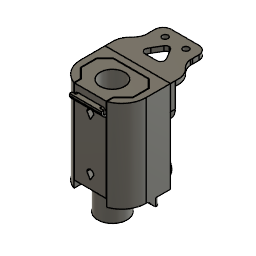
GCodeScribe-Ai3MS-v2 (Autodesk Fusion 360 design; units mm, degrees)
Autodesk Fusion 360 part; units mm, degrees
sketch "Skizze1" plane through (0, 0, 0) normal (0, 0, 1) x (1, 0, 0)
  circle A0 centre (-21.4, -45) radius 3
  circle A1 centre (10.4, -45) radius 3
  line L0 (10.4, -17.9) -> (12.7094, -15.1149)
  line L1 (10.4, -17.9) -> (8.0906, -15.1149)
  line L2 (10.4, -47.9) -> (11.8113, -46.1172)
  line L3 (10.4, -47.9) -> (8.9887, -46.1172)
  line L4 (-21.4, -47.9) -> (-19.9887, -46.1172)
  line L5 (-21.4, -47.9) -> (-22.8113, -46.1172)
  line L6 (0, 3) -> (20, 3)
  line L7 (0, 3) -> (-20, 3)
  line L8 (0, -52.5) -> (10, -52.5)
  line L9 (0, -52.5) -> (-21, -52.5)
  line L10 (-18, -16) -> (-18, -9)
  line L11 (-20, 3) -> (-20, -2)
  line L12 (20, 3) -> (20, -12)
  spline S0 degree 5 poles (-20, -2) (-19.9962, -2.1382) (-19.9821, -2.4102) (-19.9417, -2.805) (-19.8459, -3.3161) (-19.6426, -3.9884) (-19.3553, -4.7231) (-18.9981, -5.5245) (-18.6487, -6.2255) (-18.379, -6.7307) (-18.1914, -7.1991) (-18.0954, -7.7141) (-18.042, -8.2765) (-18.0129, -8.7435) (-18, -9) knots 0 0 0 0 0 0 0.1 0.2 0.3 0.4 0.5 0.6 0.7 0.8 0.9 1 1 1 1 1 1
  line L13 (-19.3517, -4.7497) -> (-18.6483, -6.2503)
  line L14 (-20.0191, -1.3059) -> (-19.9809, -2.6941)
  line L15 (-18.065, -7.7085) -> (-17.935, -10.2915)
  spline S1 degree 5 poles (-18, -16) (-18.0015, -16.1229) (-18.0072, -16.3686) (-18.0241, -16.7364) (-18.0635, -17.2253) (-18.1429, -17.8339) (-18.255, -18.4398) (-18.4023, -19.0426) (-18.5862, -19.6424) (-18.805, -20.2392) (-19.0559, -20.8333) (-19.2802, -21.3065) (-19.4608, -21.6604) (-19.5866, -21.8959) (-19.6509, -22.0135) knots 0 0 0 0 0 0 0.1 0.2 0.3 0.4 0.5 0.6 0.7 0.8 0.9 1 1 1 1 1 1
  spline S2 degree 5 poles (-21.2455, -30.2376) (-21.2309, -30.4269) (-21.205, -30.8022) (-21.1761, -31.3543) (-21.1617, -32.0688) (-21.2087, -32.9229) (-21.3505, -33.7345) (-21.6131, -34.4999) (-22.0109, -35.2163) (-22.5348, -35.8831) (-23.1534, -36.5016) (-23.8233, -37.0744) (-24.4963, -37.6045) (-25.1269, -38.0951) (-25.6805, -38.5493) (-26.1397, -38.9694) (-26.426, -39.2798) (-26.5947, -39.4985) (-26.6869, -39.6381) (-26.728, -39.7064) knots 0 0 0 0 0 0 0.066667 0.133333 0.2 0.266667 0.333333 0.4 0.466667 0.533333 0.6 0.666667 0.733333 0.8 0.866667 0.933333 1 1 1 1 1 1
  line L16 (-21.3577, -28.7828) -> (-21.1334, -31.6924)
  spline S3 degree 5 poles (20, -12) (19.9902, -12.2537) (19.9583, -12.7517) (19.8731, -13.4705) (19.6847, -14.3722) (19.3259, -15.4053) (18.8498, -16.3464) (18.2695, -17.2007) (17.6094, -17.9783) (16.9043, -18.6958) (16.1934, -19.3801) (15.5157, -20.0708) (14.9046, -20.8255) (14.3839, -21.7174) (13.9694, -22.8146) (13.6688, -24.1621) (13.4822, -25.7646) (13.4024, -27.5617) (13.4166, -29.4387) (13.5126, -31.2683) (13.6808, -32.9342) (13.9233, -34.3811) (14.247, -35.6094) (14.6958, -36.8028) (15.2662, -38.0648) (15.8927, -39.3316) (16.3745, -40.2602) (16.6918, -40.8543) (16.8792, -41.197) (16.9669, -41.3551) knots 0 0 0 0 0 0 0.04 0.08 0.12 0.16 0.2 0.24 0.28 0.32 0.36 0.4 0.44 0.48 0.52 0.56 0.6 0.64 0.68 0.72 0.76 0.8 0.84 0.88 0.92 0.96 1 1 1 1 1 1
  line L17 (15.8541, -39.3501) -> (18.0798, -43.3601)
  line L18 (13.4229, -32.7877) -> (15.038, -38.1064)
  arc A2 (-19.3409, -21.4198) -> (-21.2455, -30.2376) centre (-5.5, -29.024) ccw
  arc A3 (-26.728, -39.7064) -> (-21, -52.5) centre (-21.4, -45) ccw
  arc A4 (10, -52.5) -> (16.9669, -41.3551) centre (10.4, -45) ccw
  arc A5 (12.7094, -15.1149) -> (8.0906, -15.1149) centre (10.4, -13.2) ccw
  arc A6 (11.8113, -46.1172) -> (8.9887, -46.1172) centre (10.4, -45) ccw
  arc A7 (-19.9887, -46.1172) -> (-22.8113, -46.1172) centre (-21.4, -45) ccw
  line L19 (-5.5, -46) -> (2.9593, -36.8144)
  line L20 (-5.5, -46) -> (-13.9593, -36.8144)
  arc A8 (2.9593, -36.8144) -> (-13.9593, -36.8144) centre (-5.5, -29.024) ccw
  point P0 (-19, -5.5)
  point P1 (-18.4, -19)
  point P2 (-21.8, -34.8)
  point P3 (-25, -38)
  point P4 (18.5235, -16.7998)
  point P5 (15.7176, -19.8821)
  point P6 (13.6059, -24.8553)
  point P7 (14.2304, -35.447)
  dimension "d1" = 3
  dimension "d4" = 52.5
  dimension "d5" = 31.8
  dimension "d6" = 6
  dimension "d7" = 6
  constraint concentric A0 A7
  constraint concentric A1 A6
  constraint tangent L0 A5
  constraint tangent L1 A5
  constraint tangent L2 A6
  constraint tangent L3 A6
  constraint tangent L4 A7
  constraint tangent L5 A7
  constraint perpendicular L7 L10
  constraint perpendicular L7 L11
  constraint perpendicular L6 L12
  constraint midpoint P0 L13
  constraint midpoint L11.end L14
  constraint midpoint L10.end L15
  constraint concentric A2 A8
  constraint coincident S1.end A2
  constraint concentric A0 A3
  constraint concentric A4 A6
  constraint midpoint S2.start L16
  constraint tangent L16 A2
  constraint midpoint S3.end L17
  constraint tangent L17 A4
  constraint midpoint P7 L18
  constraint coincident S1 A2.start
  constraint tangent L19 A8
  constraint tangent L20 A8
  measures "d1" distance of origin L6.start
  measures "d4" distance of origin L8.start
  measures "d5" distance of A1.centre A0.centre
  measures "d6" diameter of A0
  measures "d7" diameter of A1
extrude "Extrusion1" add sketch "Skizze1" against normal blind 3 contours L6 L7 L8 L9 L10 L11 L12 S0 S1 S2 S3 A2 A3 A4 makes body 1
extrude "Extrusion2" add sketch "Skizze1" along normal blind -3 and the other way blind 1 contours A0 | A1 bodies 1
chamfer "Fase1" distance 1 angle 45 2 edges at (-24.197, -43.9152, 0) (7.603, -43.9152, 0) tangent chain off on bodies 1
sketch "Skizze3" plane through (0, 3, 0) normal (0, 1, 0) x (-1, 0, 0)
  line L0 (20, 0) -> (-20, 0)
  line L1 (-20, 0) -> (-20, -3)
  line L2 (-20, -3) -> (20, -3)
  line L3 (20, -3) -> (20, 0)
  circle A0 centre (6.3, -23.1) radius 1.8
  circle A1 centre (-6.35, -23.1) radius 1.8
  line L4 (13.5, -18.7516) -> (13.5, -24)
  spline S0 degree 5 poles (8.5, -29) (8.6225, -29) (8.8744, -28.9898) (9.2731, -28.944) (9.8406, -28.8204) (10.5757, -28.5537) (11.2933, -28.1664) (11.9495, -27.6548) (12.5089, -27.0273) (12.9534, -26.312) (13.2741, -25.5451) (13.4289, -24.9193) (13.4871, -24.4559) (13.5, -24.1512) (13.5, -24) knots 0 0 0 0 0 0 0.1 0.2 0.3 0.4 0.5 0.6 0.7 0.8 0.9 1 1 1 1 1 1
  line L5 (13.5, -24.8) -> (13.5, -23.2)
  line L6 (7.8, -29) -> (9.2, -29)
  spline S1 degree 5 poles (13.5, -20) (13.5, -19.9292) (13.4971, -19.7541) (13.4842, -19.3915) (13.4737, -18.7163) (13.5884, -17.6135) (13.9445, -16.3468) (14.5844, -15.0442) (15.4313, -13.8595) (16.179, -12.9859) (16.756, -12.4009) (17.1969, -11.9798) (17.5969, -11.5513) (18.0425, -10.9683) (18.5401, -10.1859) (19.0328, -9.246) (19.447, -8.2461) (19.7218, -7.2982) (19.8588, -6.5279) (19.9339, -5.9739) (19.9737, -5.4171) (19.9917, -4.7412) (19.9985, -3.9829) (20, -3.3491) (20, -3) knots 0 0 0 0 0 0 0.05 0.1 0.15 0.2 0.25 0.3 0.35 0.4 0.45 0.5 0.55 0.6 0.65 0.7 0.75 0.8 0.85 0.9 0.95 1 1 1 1 1 1
  line L7 (20, -7) -> (20, 1)
  line L8 (13.3963, -16.8526) -> (16.6037, -12.1474)
  line L9 (13.5, -20.6696) -> (13.5, -19.3304)
  line L10 (19.3454, -8.9015) -> (20.128, -5.3644)
  line L11 (8.5, -29) -> (0, -29)
  line L12 (0, -29) -> (0, 0)
  line L13 (-8.5, -29) -> (0, -29)
  spline S2 degree 5 poles (-8.5, -29) (-8.6225, -29) (-8.8744, -28.9898) (-9.2731, -28.944) (-9.8406, -28.8204) (-10.5757, -28.5537) (-11.2933, -28.1664) (-11.9495, -27.6548) (-12.5089, -27.0273) (-12.9534, -26.312) (-13.2741, -25.5451) (-13.4289, -24.9193) (-13.4871, -24.4559) (-13.5, -24.1512) (-13.5, -24) knots 0 0 0 0 0 0 0.1 0.2 0.3 0.4 0.5 0.6 0.7 0.8 0.9 1 1 1 1 1 1
  line L14 (-7.8, -29) -> (-9.2, -29)
  line L15 (-13.5, -24.8) -> (-13.5, -23.2)
  line L16 (-13.5, -18.7516) -> (-13.5, -24)
  spline S3 degree 5 poles (-13.5, -20) (-13.5, -19.9292) (-13.4971, -19.7541) (-13.4842, -19.3915) (-13.4737, -18.7163) (-13.5884, -17.6135) (-13.9445, -16.3468) (-14.5844, -15.0442) (-15.4313, -13.8595) (-16.179, -12.9859) (-16.756, -12.4009) (-17.1969, -11.9798) (-17.5969, -11.5513) (-18.0425, -10.9683) (-18.5401, -10.1859) (-19.0328, -9.246) (-19.447, -8.2461) (-19.7218, -7.2982) (-19.8588, -6.5279) (-19.9339, -5.9739) (-19.9737, -5.4171) (-19.9917, -4.7412) (-19.9985, -3.9829) (-20, -3.3491) (-20, -3) knots 0 0 0 0 0 0 0.05 0.1 0.15 0.2 0.25 0.3 0.35 0.4 0.45 0.5 0.55 0.6 0.65 0.7 0.75 0.8 0.85 0.9 0.95 1 1 1 1 1 1
  line L17 (-13.5, -20.6696) -> (-13.5, -19.3304)
  line L18 (-13.3963, -16.8526) -> (-16.6037, -12.1474)
  line L19 (-19.3454, -8.9015) -> (-20.128, -5.3644)
  line L20 (-20, -7) -> (-20, 1)
  line L21 (20, -3) -> (-20, -3)
  line L22 (0, -8) -> (-4, -8)
  line L23 (-5, -13) -> (-2, -18)
  spline S4 degree 5 poles (-4, -8) (-4.0989, -8) (-4.2956, -8.0243) (-4.5872, -8.1338) (-4.9651, -8.4053) (-5.3965, -8.8504) (-5.7532, -9.3091) (-5.9981, -9.7274) (-6.0873, -10.2022) (-6.0148, -10.7812) (-5.7969, -11.4575) (-5.5261, -12.0559) (-5.279, -12.5228) (-5.096, -12.8399) (-5, -13) knots 0 0 0 0 0 0 0.1 0.2 0.3 0.4 0.5 0.6 0.7 0.8 0.9 1 1 1 1 1 1
  spline S5 degree 5 poles (-2, -18) (-1.9518, -18.067) (-1.8575, -18.1956) (-1.7217, -18.372) (-1.5525, -18.5738) (-1.3612, -18.7681) (-1.1888, -18.9058) (-1.0316, -18.9925) (-0.8802, -19.0487) (-0.7186, -19.1024) (-0.5304, -19.153) (-0.3459, -19.1844) (-0.1831, -19.1972) (-0.063, -19.2) (0, -19.2) knots 0 0 0 0 0 0 0.1 0.2 0.3 0.4 0.5 0.6 0.7 0.8 0.9 1 1 1 1 1 1
  line L24 (-0.3974, -19.2) -> (0.3974, -19.2)
  line L25 (-1.1683, -18.9262) -> (-0.8317, -19.0738)
  line L26 (-3.5, -8) -> (-4.5, -8)
  line L27 (-5.4264, -12.2893) -> (-4.5736, -13.7107)
  line L28 (-5.7067, -9.1954) -> (-6.0933, -10.0046)
  spline S6 degree 5 poles (2, -18) (1.9518, -18.067) (1.8575, -18.1956) (1.7217, -18.372) (1.5525, -18.5738) (1.3612, -18.7681) (1.1888, -18.9058) (1.0316, -18.9925) (0.8802, -19.0487) (0.7186, -19.1024) (0.5304, -19.153) (0.3459, -19.1844) (0.1831, -19.1972) (0.063, -19.2) (0, -19.2) knots 0 0 0 0 0 0 0.1 0.2 0.3 0.4 0.5 0.6 0.7 0.8 0.9 1 1 1 1 1 1
  line L29 (-2.2394, -17.6668) -> (-1.7606, -18.3332)
  line L30 (2.2394, -17.6668) -> (1.7606, -18.3332)
  line L31 (1.1683, -18.9262) -> (0.8317, -19.0738)
  line L32 (0.3974, -19.2) -> (-0.3974, -19.2)
  line L33 (5, -13) -> (2, -18)
  spline S7 degree 5 poles (4, -8) (4.0989, -8) (4.2956, -8.0243) (4.5872, -8.1338) (4.9651, -8.4053) (5.3965, -8.8504) (5.7532, -9.3091) (5.9981, -9.7274) (6.0873, -10.2022) (6.0148, -10.7812) (5.7969, -11.4575) (5.5261, -12.0559) (5.279, -12.5228) (5.096, -12.8399) (5, -13) knots 0 0 0 0 0 0 0.1 0.2 0.3 0.4 0.5 0.6 0.7 0.8 0.9 1 1 1 1 1 1
  line L34 (3.5, -8) -> (4.5, -8)
  line L35 (5.7067, -9.1954) -> (6.0933, -10.0046)
  line L36 (5.4264, -12.2893) -> (4.5736, -13.7107)
  line L37 (0, -8) -> (4, -8)
  point P0 (11.8587, -27.6874)
  point P1 (15, -14.5)
  point P2 (17.7, -11.4)
  point P3 (19.7367, -7.1329)
  point P4 (-11.8587, -27.6874)
  point P5 (-15, -14.5)
  point P6 (-17.7, -11.4)
  point P7 (-19.7367, -7.1329)
  point P8 (-5.9, -9.6)
  point P9 (-1, -19)
  point P10 (1, -19)
  point P11 (5.9, -9.6)
  dimension "d15" = 12.65
  dimension "d16" = 3.6
  constraint midpoint L4.end L5
  constraint midpoint S0.start L6
  constraint coincident L4 S1.start
  constraint midpoint L2.end L7
  constraint midpoint P1 L8
  constraint midpoint S1.start L9
  constraint coincident S1 L4.start
  constraint midpoint P3 L10
  constraint parallel L2 L11
  constraint coincident L12.end origin
  constraint perpendicular L0 L12
  constraint symmetric S0.start L12 L13.start
  constraint symmetric P0 L12 P4
  constraint symmetric L4.end L12 S2.end
  constraint symmetric L5.start L12 L15.start
  constraint symmetric L5.end L12 L15.end
  constraint symmetric L6.start L12 L14.start
  constraint symmetric L6.end L12 L14.end
  constraint symmetric S1.start L12 S3.start
  constraint symmetric P1 L12 P5
  constraint symmetric P2 L12 P6
  constraint symmetric P3 L12 P7
  constraint symmetric L2.end L12 L1.end
  constraint symmetric L7.start L12 L20.start
  constraint symmetric L7.end L12 L20.end
  constraint symmetric L8.start L12 L18.start
  constraint symmetric L8.end L12 L18.end
  constraint symmetric L9.start L12 L17.start
  constraint symmetric L9.end L12 L17.end
  constraint symmetric L4.start L12 L16.start
  constraint symmetric L10.start L12 L19.start
  constraint symmetric L10.end L12 L19.end
  constraint symmetric L11.end L12 L13.end
  constraint coincident L12 L22.start
  constraint perpendicular L12 L22
  constraint coincident L12 S5.end
  constraint midpoint S5.end L24
  constraint midpoint P9 L25
  constraint midpoint L22.end L26
  constraint midpoint L23.start L27
  constraint coincident L23 L27.end
  constraint midpoint P8 L28
  constraint midpoint L23.end L29
  constraint symmetric L12 L22.start L37.start
  constraint symmetric L12 L22.end S7.start
  constraint symmetric L12 L23.start L33.start
  constraint symmetric L12 L23.end S6.start
  constraint symmetric L12 P8 P11
  constraint symmetric L12 P9 P10
  constraint symmetric L12 S5.end S6.end
  constraint symmetric L12 L24.start L24.end
  constraint symmetric L12 L24.end L24.start
  constraint symmetric L12 L25.start L31.start
  constraint symmetric L12 L25.end L31.end
  constraint symmetric L12 L26.start L34.start
  constraint symmetric L12 L26.end L34.end
  constraint symmetric L12 L27.start L36.start
  constraint symmetric L12 L27.end L36.end
  constraint symmetric L12 L28.start L35.start
  constraint symmetric L12 L28.end L35.end
  constraint symmetric L12 L29.start L30.start
  constraint symmetric L12 L29.end L30.end
  measures "d15" distance of A0.centre A1.centre
  measures "d16" diameter of A1
extrude "Extrusion3" add sketch "Skizze3" against normal blind 3 contours L2 L4 S0 L5 L6 S1 L9 L11 L12 L21 S6 L33 S7 L34 L36 L37 | L2 L12 L13 S2 L14 L15 L16 S3 L17 L21 L22 L23 S4 S5 L26 L27 bodies 1
sketch "Skizze4" plane through (0, 0, 0) normal (0, 0, 1) x (1, 0, 0)
  circle A0 centre (-21.4, -45) radius 4
  line L0 (12.7094, -15.1149) -> (10.4, -17.9)
  line L1 (10.4, -17.9) -> (8.0906, -15.1149)
  arc A1 (12.7094, -15.1149) -> (8.0906, -15.1149) centre (10.4, -13.2) ccw
  line L2 (-21, -52.5) -> (10, -52.5)
  arc A2 (10, -52.5) -> (16.9669, -41.3551) centre (10.4, -45) ccw
  spline S0 degree 5 poles (20, -12) (19.9902, -12.2537) (19.9583, -12.7517) (19.8731, -13.4705) (19.6847, -14.3722) (19.3259, -15.4053) (18.8498, -16.3464) (18.2695, -17.2007) (17.6094, -17.9783) (16.9043, -18.6958) (16.1934, -19.3801) (15.5157, -20.0708) (14.9046, -20.8255) (14.3839, -21.7174) (13.9694, -22.8146) (13.6688, -24.1621) (13.4822, -25.7646) (13.4024, -27.5617) (13.4166, -29.4387) (13.5126, -31.2683) (13.6808, -32.9342) (13.9233, -34.3811) (14.247, -35.6094) (14.6958, -36.8028) (15.2662, -38.0648) (15.8927, -39.3316) (16.3745, -40.2602) (16.6918, -40.8543) (16.8792, -41.197) (16.9669, -41.3551) knots 0 0 0 0 0 0 0.04 0.08 0.12 0.16 0.2 0.24 0.28 0.32 0.36 0.4 0.44 0.48 0.52 0.56 0.6 0.64 0.68 0.72 0.76 0.8 0.84 0.88 0.92 0.96 1 1 1 1 1 1
  line L3 (20, -12) -> (20, 3)
  line L4 (20, 3) -> (-20, 3)
  line L5 (-20, 3) -> (-20, -2)
  spline S1 degree 5 poles (-20, -2) (-19.9962, -2.1382) (-19.9821, -2.4102) (-19.9417, -2.805) (-19.8459, -3.3161) (-19.6426, -3.9884) (-19.3553, -4.7231) (-18.9981, -5.5245) (-18.6487, -6.2255) (-18.379, -6.7307) (-18.1914, -7.1991) (-18.0954, -7.7141) (-18.042, -8.2765) (-18.0129, -8.7435) (-18, -9) knots 0 0 0 0 0 0 0.1 0.2 0.3 0.4 0.5 0.6 0.7 0.8 0.9 1 1 1 1 1 1
  line L6 (-18, -9) -> (-18, -16)
  spline S2 degree 5 poles (-18, -16) (-18.0015, -16.1229) (-18.0072, -16.3686) (-18.0241, -16.7364) (-18.0635, -17.2253) (-18.1429, -17.8339) (-18.255, -18.4398) (-18.4023, -19.0426) (-18.5862, -19.6424) (-18.8046, -20.2383) (-19.0049, -20.7127) (-19.1683, -21.0671) (-19.2826, -21.3026) (-19.3409, -21.4198) knots 0 0 0 0 0 0 0.1 0.2 0.3 0.4 0.5 0.6 0.7 0.8 0.899242 0.899242 0.899242 0.899242 0.899242 0.899242
  spline S3 degree 5 poles (-19.3409, -21.4198) (-19.3414, -21.4207) (-19.4006, -21.5397) (-19.4612, -21.6585) (-19.5232, -21.7773) (-19.5866, -21.8959) (-19.6509, -22.0135) knots 0.899242 0.899242 0.899242 0.899242 0.899242 0.899242 0.9 1 1 1 1 1 1
  arc A3 (-19.6509, -22.0135) -> (-21.2455, -30.2376) centre (-5.5, -29.024) ccw
  spline S4 degree 5 poles (-21.2455, -30.2376) (-21.2309, -30.4269) (-21.205, -30.8022) (-21.1761, -31.3543) (-21.1617, -32.0688) (-21.2087, -32.9229) (-21.3505, -33.7345) (-21.6131, -34.4999) (-22.0109, -35.2163) (-22.5348, -35.8831) (-23.1534, -36.5016) (-23.8233, -37.0744) (-24.4963, -37.6045) (-25.1269, -38.0951) (-25.6805, -38.5493) (-26.1397, -38.9694) (-26.426, -39.2798) (-26.5947, -39.4985) (-26.6869, -39.6381) (-26.728, -39.7064) knots 0 0 0 0 0 0 0.066667 0.133333 0.2 0.266667 0.333333 0.4 0.466667 0.533333 0.6 0.666667 0.733333 0.8 0.866667 0.933333 1 1 1 1 1 1
  arc A4 (-26.728, -39.7064) -> (-21, -52.5) centre (-21.4, -45) ccw
  circle A5 centre (10.4, -45) radius 4
  line L7 (2.9593, -36.8144) -> (-5.5, -46)
  line L8 (-5.5, -46) -> (-13.9593, -36.8144)
  arc A6 (2.9593, -36.8144) -> (-13.9593, -36.8144) centre (-5.5, -29.024) ccw
  line L9 (2, -49.5) -> (3.7496, -47.7857)
  line L10 (2, -49.5) -> (0.2504, -47.7857)
  line L11 (10, -40.5) -> (11.7496, -38.7857)
  line L12 (10, -40.5) -> (8.2504, -38.7857)
  line L13 (10, -25.5) -> (11.7496, -23.7857)
  line L14 (10, -25.5) -> (8.2504, -23.7857)
  line L15 (14, -7.5) -> (15.7496, -5.7857)
  line L16 (14, -7.5) -> (12.2504, -5.7857)
  line L17 (-14, -7.5) -> (-12.2504, -5.7857)
  line L18 (-14, -7.5) -> (-15.7496, -5.7857)
  arc A7 (-12.2504, -5.7857) -> (-15.7496, -5.7857) centre (-14, -4) ccw
  arc A8 (15.7496, -5.7857) -> (12.2504, -5.7857) centre (14, -4) ccw
  arc A9 (11.7496, -23.7857) -> (8.2504, -23.7857) centre (10, -22) ccw
  arc A10 (11.7496, -38.7857) -> (8.2504, -38.7857) centre (10, -37) ccw
  arc A11 (3.7496, -47.7857) -> (0.2504, -47.7857) centre (2, -46) ccw
  arc A12 (-11.2504, -47.7857) -> (-14.7496, -47.7857) centre (-13, -46) ccw
  line L19 (-13, -49.5) -> (-11.2504, -47.7857)
  line L20 (-13, -49.5) -> (-14.7496, -47.7857)
  dimension "d20" = 5
  dimension "d21" = 5
  dimension "d22" = 5
  dimension "d23" = 5
  dimension "d29" = 3.5
  dimension "d30" = 3.5
  dimension "d31" = 3.5
  dimension "d32" = 3.5
  dimension "d33" = 3.5
  dimension "d125" = 5
  dimension "d126" = 3.5
  constraint tangent L9 A11
  constraint tangent L10 A11
  constraint tangent L11 A10
  constraint tangent L12 A10
  constraint tangent L13 A9
  constraint tangent L14 A9
  constraint tangent L15 A8
  constraint tangent L16 A8
  constraint tangent L17 A7
  constraint tangent L18 A7
  constraint tangent A12 L19
  constraint tangent A12 L20
  measures "d20" diameter of A9
  measures "d21" diameter of A8
  measures "d22" diameter of A7
  measures "d23" diameter of A11
  measures "d29" distance of A9.centre L13.start
  measures "d30" distance of A8.centre L15.start
  measures "d31" distance of A7.centre L17.start
  measures "d32" distance of A10.centre L11.start
  measures "d33" distance of A11.centre L9.start
  measures "d125" diameter of A12
  measures "d126" distance of A12.centre L19.start
extrude "Extrusion4" cut sketch "Skizze4" against normal blind 2 contours L9 L10 A11 | L11 L12 A10 | L13 L14 A9 | L15 L16 A8 | L17 L18 A7 | A12 L19 L20 bodies 1
chamfer "Fase2" distance 0.3 angle 45 18 edges at (1.1252, -48.6429, 0) (2, -43.5, 0) (2.8748, -48.6429, 0) (9.1252, -39.6429, 0) (10, -34.5, 0) (10.8748, -39.6429, 0) (9.1252, -24.6429, 0) (10, -19.5, 0) (10.8748, -24.6429, 0) (13.1252, -6.6429, 0) (14, -1.5, 0) (14.8748, -6.6429, 0) (-13.1252, -6.6429, 0) (-14, -1.5, 0) (-14.8748, -6.6429, 0) (-13, -43.5, 0) (-12.1252, -48.6429, 0) (-13.8748, -48.6429, 0) tangent chain off on bodies 1
sketch "Skizze6" plane through (0, 0, 0) normal (0, 0, 1) x (1, 0, 0)
  line L0 (-20, 0) -> (-20, -53)
  line L1 (-20, -53) -> (20, -53)
  line L2 (20, -53) -> (20, 0)
  line L3 (-20, 0) -> (-20, 3)
  line L4 (-20, 3) -> (20, 3)
  line L5 (20, 3) -> (20, 0)
  line L6 (-20, -50) -> (20, -50)
  line L7 (-20, 3) -> (-20, 6)
  line L8 (-20, 6) -> (20, 6)
  line L9 (20, 6) -> (20, 3)
  constraint vertical L0
  constraint horizontal L1
  constraint vertical L2
  constraint perpendicular L3 L4
  constraint coincident L0 L6.start
  constraint coincident L2 L6.end
  constraint perpendicular L2 L6
  constraint perpendicular L4 L7
  constraint perpendicular L3 L8
  constraint perpendicular L4 L9
extrude "Extrusion8" add sketch "Skizze6" along normal blind 4 separate body contours L0 L2 L3 L4 L5 L6 | L0 L1 L2 L6 makes body 2
extrude "Extrusion9" cut sketch "Skizze1" along normal blind 3 contours A0 | A1 | L0 L1 A5 | L2 L3 A6 | L4 L5 A7 bodies 2
extrude "Extrusion10" cut sketch "Skizze4" along normal blind 2.5 contours L9 L10 A11 | L11 L12 A10 | L13 L14 A9 | L15 L16 A8 | L17 L18 A7 | A12 L19 L20 bodies 2
chamfer "Fase3" distance 0.5 angle 45 18 edges at (14.8748, -6.6429, 0) (14, -1.5, 0) (13.1252, -6.6429, 0) (10, -19.5, 0) (9.1252, -24.6429, 0) (10.8748, -24.6429, 0) (10, -34.5, 0) (9.1252, -39.6429, 0) (10.8748, -39.6429, 0) (2, -43.5, 0) (1.1252, -48.6429, 0) (2.8748, -48.6429, 0) (-13, -43.5, 0) (-13.8748, -48.6429, 0) (-12.1252, -48.6429, 0) (-14, -1.5, 0) (-14.8748, -6.6429, 0) (-13.1252, -6.6429, 0) tangent chain off on bodies 2
chamfer "Fase3" distance 0.5 angle 45 5 edges at (7.603, -46.0848, 0) (10.4, -10.2, 0) (9.2453, -16.5074, 0) (11.5547, -16.5074, 0) (-18.4, -45, 0) tangent chain off on bodies 2
sketch "Skizze7" plane through (0, 3, 0) normal (0, 1, 0) x (-1, 0, 0)
  line L0 (-20, 0) -> (20, 0)
  line L1 (20, 0) -> (20, 4)
  line L2 (20, 4) -> (-20, 4)
  line L3 (-20, 4) -> (-20, 0)
  line L4 (16, 4) -> (16, 25)
  line L5 (16, 25) -> (10, 25)
  line L6 (10, 25) -> (10, 29)
  line L7 (0, 8) -> (0, 23)
  arc A0 (0, 8) -> (0, 23) centre (0, 15.5) ccw
  line L8 (15.75, 4.25) -> (15.75, 24.75)
  line L9 (15.75, 24.75) -> (9.75, 24.75)
  line L10 (9.75, 24.75) -> (9.75, 29)
  line L11 (20, 4) -> (16, 4)
  line L12 (0, 8) -> (0, 4.25)
  line L13 (0, 4.25) -> (15.75, 4.25)
  line L14 (0, 4.25) -> (-15.75, 4.25)
  line L15 (-15.75, 4.25) -> (-15.75, 24.75)
  line L16 (-15.75, 24.75) -> (-9.75, 24.75)
  line L17 (-9.75, 24.75) -> (-9.75, 29)
  arc A1 (0, 23) -> (0, 8) centre (0, 15.5) ccw
  line L18 (-10, 25) -> (-10, 29)
  line L19 (-16, 25) -> (-10, 25)
  line L20 (-16, 4) -> (-16, 25)
  line L21 (-16, 4) -> (-20, 4)
  circle A2 centre (0, 15.5) radius 9
  line L22 (10, 25) -> (10, 4)
  line L23 (-10, 25) -> (-10, 4)
  line L24 (-10, 29) -> (-20, 29)
  line L25 (20, 4) -> (20, 29)
  line L26 (20, 29) -> (10, 29)
  line L27 (-20, 29) -> (-20, 4)
  line L28 (9.75, 29) -> (-9.75, 29)
  dimension "d50" = 3.75
  dimension "d74" = 18
  constraint coincident L1.end L2.start
  constraint coincident L2 L4.start
  constraint perpendicular L4 L5
  constraint perpendicular L5 L6
  constraint perpendicular L2 L7
  constraint perpendicular L4 L11
  constraint perpendicular L2 L12
  constraint perpendicular L8 L13
  constraint symmetric L7 A0.end A1.start
  constraint symmetric L7 A0.start L12.start
  constraint symmetric L7 A0 A1
  constraint symmetric L7 L8.end L15.end
  constraint symmetric L7 L9.end L16.end
  constraint symmetric L7 L10.end L17.end
  constraint symmetric L7 L12.end L13.start
  constraint symmetric L7 L8.start L14.end
  constraint symmetric L1.end L12 L2.end
  constraint symmetric L4.start L12 L20.start
  constraint symmetric L4.end L12 L19.start
  constraint symmetric L5.end L12 L18.start
  constraint symmetric L6.end L12 L18.end
  constraint concentric A1 A2
  constraint coincident L2 L22.end
  constraint perpendicular L2 L22
  constraint coincident L2 L23.end
  constraint perpendicular L2 L23
  constraint perpendicular L10 L26
  constraint perpendicular L2 L27
  constraint perpendicular L17 L28
  measures "d50" distance of L7.start L12.end
  measures "d74" diameter of A2
extrude "Extrusion11" add sketch "Skizze7" against normal blind 56 contours L2 L18 L19 L20 L21 L24 L27 | L2 L4 L5 L6 L11 L25 L26 bodies 2
extrude "Extrusion12" add sketch "Skizze7" against normal blind 51.5 separate body contours L9 L10 L13 L14 L16 L17 L22 L23 L28 | L14 L15 L16 L23 | L8 L9 L13 L22 | A2 makes body 3
sketch "Skizze8" plane through (0, 0, 0) normal (0, 0, 1) x (1, 0, 0)
  line L0 (-2.1, -8) -> (-0.0298, -11.5421)
  line L1 (-2.1, -8) -> (2.9381, -8) construction
  line L2 (2.1, -8) -> (-0.0298, -11.5421)
  line L3 (2.1, -8) -> (6.7668, -8) construction
  arc A0 (2.1, -8) -> (-2.1, -8) centre (0, -8) ccw
  line L4 (2.1, -40) -> (-0.0298, -43.5421)
  arc A1 (2.1, -40) -> (-2.1, -40) centre (0, -40) ccw
  line L5 (-2.1, -40) -> (-0.0298, -43.5421)
  line L6 (-9.75, -5) -> (-9.75, -1.0528)
  line L7 (9.75, -1.0528) -> (9.75, -5)
  line L8 (-9.75, -1.0528) -> (9.75, -1.0528)
  line L9 (9.75, -5) -> (-9.75, -5)
  dimension "d93" = 0
  dimension "d94" = -32
  constraint horizontal L1
  constraint horizontal L3
  constraint perpendicular L7 L8
  constraint perpendicular L6 L9
extrude "Extrusion13" cut sketch "Skizze8" along normal blind 29 and the other way blind -22 contours L0 L2 A0 | L4 A1 L5 bodies 3
extrude "Extrusion14" add sketch "Skizze7" along normal blind -56 and the other way blind 52 contours L2 L14 L15 L16 L19 L20 L23 | L2 L4 L5 L8 L9 L13 L22 | L14 L15 L16 L23 | L8 L9 L13 L22 bodies 2
extrude "Extrusion15" add sketch "Skizze7" along normal blind -51.5 and the other way blind 70 contours A2 bodies 3
extrude "Extrusion16" add sketch "Skizze8" along normal blind 29 and the other way blind -30.5 contours L6 L7 L8 L9 bodies 3
fillet "Abrundung5" radius 2.5 2 edges at (-9.75, -1.0528, 29.75) (9.75, -1.0528, 29.75) on bodies 3
extrude "Extrusion17" add sketch "Skizze8" along normal blind 30.5 and the other way blind -32 contours L6 L7 L8 L9 bodies 3
chamfer "Fase5" distance 2 angle 45 1 edges at (0, -5, 32) tangent chain off on bodies 3
fillet "Abrundung6" radius 1.65 2 edges at (0, -3, 32) (0, -5, 30) on bodies 3
fillet "Abrundung6" radius 0.8 1 edges at (0, -5, 29) on bodies 3
fillet "Abrundung3" radius 7 2 edges at (10, -51, 4) (-10, -51, 4) on bodies 2
chamfer "Fase4" distance 5 angle 45 2 edges at (15.75, -22.75, 4.25) (-15.75, -22.75, 4.25) tangent chain off on bodies 2 3
chamfer "Fase4" distance 5 angle 45 2 edges at (16, -23, 4) (-16, -23, 4) tangent chain off on bodies 2 3
chamfer "Fase4" distance 6 angle 45 2 edges at (-15.75, -22.75, 24.75) (15.75, -22.75, 24.75) tangent chain off on bodies 2 3
chamfer "Fase4" distance 6 angle 45 2 edges at (-16, -23, 25) (16, -23, 25) tangent chain off on bodies 2 3
fillet "Abrundung4" radius 15 2 edges at (20, -25, 29) (-20, -25, 29) on bodies 2
sketch "Skizze9" plane through (0, -53, 0) normal (0, -1, 0) x (1, 0, 0)
  arc A0 (-10, 29) -> (-20, 14.8579) centre (-5, 14.8579) ccw
  line L0 (-20, 14.8579) -> (-20, 4)
  line L1 (-20, 4) -> (-20, 0)
  line L2 (-20, 0) -> (20, 0)
  line L3 (20, 0) -> (20, 14.8579)
  arc A1 (20, 14.8579) -> (10, 29) centre (5, 14.8579) ccw
  line L4 (10, 29) -> (10, 11)
  arc A2 (3, 4) -> (10, 11) centre (3, 11) ccw
  line L5 (3, 4) -> (-3, 4)
  arc A3 (-10, 11) -> (-3, 4) centre (-3, 11) ccw
  line L6 (-10, 11) -> (-10, 29)
  line L7 (20, 6) -> (10, 6)
  line L8 (20, 12) -> (20, 6)
  line L9 (0, 0) -> (0, 20)
  line L10 (10, 12) -> (20, 12)
  line L11 (-10, 12) -> (-20, 12)
  line L12 (-20, 12) -> (-20, 6)
  line L13 (-20, 6) -> (-10, 6)
  line L14 (-10, 6) -> (-7.9497, 6.0503)
  line L15 (10, 6) -> (7.899, 6)
  constraint coincident L3 L7.start
  constraint perpendicular L3 L7
  constraint coincident L4 L10.start
  constraint coincident L3 L8.start
  constraint coincident L9.start origin
  constraint perpendicular L2 L9
  constraint perpendicular L8 L10
  constraint symmetric L7.start L9 L12.end
  constraint symmetric L7.end L9 L13.end
  constraint symmetric L10.start L9 L11.start
  constraint symmetric L8.start L9 L11.end
  constraint midpoint A3 L14.end
  constraint coincident A2 L15.end
extrude "Extrusion18" add sketch "Skizze9" along normal blind 5 contours L0 A3 L6 L11 L12 L13 L14 | L3 L4 A2 L7 L8 L10 L15 bodies 2
chamfer "Fase6" distance 3 angle 45 2 edges at (-15, -58, 12) (15, -58, 12) tangent chain off on bodies 2
delete_face "Fläche löschen1" 1 faces at (-20, -55.3333, 9) on bodies 2
delete_face "Fläche löschen2" 1 faces at (-9.3166, -54.6667, 6.0168) on bodies 2
fillet "Abrundung7" radius 3.75 2 edges at (14.8541, -58, 9) (-14.8541, -58, 9) on bodies 2
fillet "Abrundung7" radius 0.25 2 edges at (7.899, -55.5, 6) (-7.899, -55.5, 6) on bodies 2
fillet "Abrundung7" radius 2.5 2 edges at (15, -55, 12) (-15, -55, 12) on bodies 2
fillet "Abrundung7" radius 3 2 edges at (-15, -53, 12) (15, -53, 12) on bodies 2
fillet "Abrundung7" radius 3 2 edges at (20, -55.5, 6) (-20, -55.5, 6) on bodies 2
equation "d50 = 4.000 mm - 0.25 mm"
equation "d54 = -56.00 mm + 4.5 mm"
equation "d74 = 15.000 mm + 3 mm"
equation "d77 = 56.00 mm - 4 mm"
named bodies: "mount", "plate", "pen"
